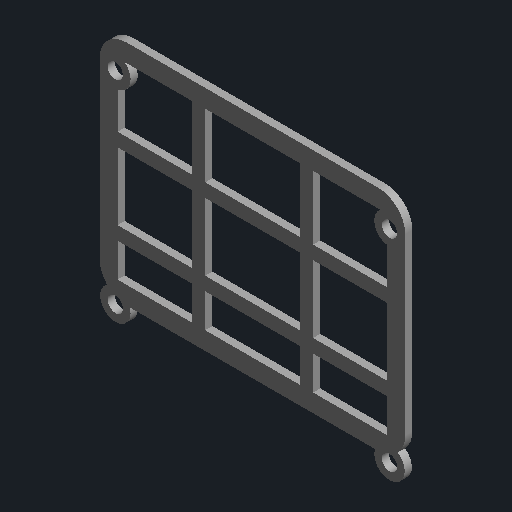
# Autodesk Inventor part: Torso_protector_B
Saved by Autodesk Inventor 2027 (Build 310192060, 192F)
## iProperties
Part Number: Torso_protector_B
Material: Genérico
Document SubType Name: Modelado
Designer: rodri
Appearance: Por defecto
Author: rodri
Autodesk Inventor part; units mm, degrees
ref_plane "Plano de trabajo1" through (0, 0, -29.6) normal (0, 0, 1) x (1, 0, 0)
sketch "Boceto1" plane through (0, 0, -29.6) normal (0, 0, 1) x (1, 0, 0)
  line L0 (-34, 7) -> (34, 7)
  line L1 (34, 7) -> (34, 57.7)
  line L2 (34, 57.7) -> (-34, 57.7)
  line L3 (-34, 57.7) -> (-34, 7)
  constraints: 8 end point, 2 parallel, 1 horizontal, 1 perpendicular
extrude "Extrusión1" add sketch "Boceto1" along normal blind 1.6
fillet "Empalme1" radius 6 4 edges at (-34, 7, -28.8) (-34, 57.7, -28.8) (34, 57.7, -28.8) (34, 7, -28.8)
ref_plane "Plano de trabajo2" through (0, 0, -29.7) normal (0, 0, 1) x (1, 0, 0)
sketch "Boceto2" plane through (0, 0, -29.7) normal (0, 0, 1) x (1, 0, 0)
  line L0 (-30, 11) -> (-13.5, 11)
  line L1 (-13.5, 11) -> (-13.5, 18.5)
  line L2 (-13.5, 18.5) -> (-30, 18.5)
  line L3 (-30, 18.5) -> (-30, 11)
  constraints: 8 end point, 2 parallel, 1 horizontal, 1 perpendicular
extrude "Extrusión2" cut sketch "Boceto2" along normal blind 1.8
ref_plane "Plano de trabajo3" through (0, 0, -29.7) normal (0, 0, 1) x (1, 0, 0)
sketch "Boceto3" plane through (0, 0, -29.7) normal (0, 0, 1) x (1, 0, 0)
  line L0 (-30, 21.5) -> (-13.5, 21.5)
  line L1 (-13.5, 21.5) -> (-13.5, 36.5)
  line L2 (-13.5, 36.5) -> (-30, 36.5)
  line L3 (-30, 36.5) -> (-30, 21.5)
  constraints: 8 end point, 2 parallel, 1 horizontal, 1 perpendicular
extrude "Extrusión3" cut sketch "Boceto3" along normal blind 1.8
ref_plane "Plano de trabajo4" through (0, 0, -29.7) normal (0, 0, 1) x (1, 0, 0)
sketch "Boceto4" plane through (0, 0, -29.7) normal (0, 0, 1) x (1, 0, 0)
  line L0 (-30, 39.5) -> (-13.5, 39.5)
  line L1 (-13.5, 39.5) -> (-13.5, 53.7)
  line L2 (-13.5, 53.7) -> (-30, 53.7)
  line L3 (-30, 53.7) -> (-30, 39.5)
  constraints: 8 end point, 2 parallel, 1 horizontal, 1 perpendicular
extrude "Extrusión4" cut sketch "Boceto4" along normal blind 1.8
ref_plane "Plano de trabajo5" through (0, 0, -29.7) normal (0, 0, 1) x (1, 0, 0)
sketch "Boceto5" plane through (0, 0, -29.7) normal (0, 0, 1) x (1, 0, 0)
  line L0 (-10.5, 11) -> (10.5, 11)
  line L1 (10.5, 11) -> (10.5, 18.5)
  line L2 (10.5, 18.5) -> (-10.5, 18.5)
  line L3 (-10.5, 18.5) -> (-10.5, 11)
  constraints: 8 end point, 2 parallel, 1 horizontal, 1 perpendicular
extrude "Extrusión5" cut sketch "Boceto5" along normal blind 1.8
ref_plane "Plano de trabajo6" through (0, 0, -29.7) normal (0, 0, 1) x (1, 0, 0)
sketch "Boceto6" plane through (0, 0, -29.7) normal (0, 0, 1) x (1, 0, 0)
  line L0 (-10.5, 21.5) -> (10.5, 21.5)
  line L1 (10.5, 21.5) -> (10.5, 36.5)
  line L2 (10.5, 36.5) -> (-10.5, 36.5)
  line L3 (-10.5, 36.5) -> (-10.5, 21.5)
  constraints: 8 end point, 2 parallel, 1 horizontal, 1 perpendicular
extrude "Extrusión6" cut sketch "Boceto6" along normal blind 1.8
ref_plane "Plano de trabajo7" through (0, 0, -29.7) normal (0, 0, 1) x (1, 0, 0)
sketch "Boceto7" plane through (0, 0, -29.7) normal (0, 0, 1) x (1, 0, 0)
  line L0 (-10.5, 39.5) -> (10.5, 39.5)
  line L1 (10.5, 39.5) -> (10.5, 53.7)
  line L2 (10.5, 53.7) -> (-10.5, 53.7)
  line L3 (-10.5, 53.7) -> (-10.5, 39.5)
  constraints: 8 end point, 2 parallel, 1 horizontal, 1 perpendicular
extrude "Extrusión7" cut sketch "Boceto7" along normal blind 1.8
ref_plane "Plano de trabajo8" through (0, 0, -29.7) normal (0, 0, 1) x (1, 0, 0)
sketch "Boceto8" plane through (0, 0, -29.7) normal (0, 0, 1) x (1, 0, 0)
  line L0 (13.5, 11) -> (30, 11)
  line L1 (30, 11) -> (30, 18.5)
  line L2 (30, 18.5) -> (13.5, 18.5)
  line L3 (13.5, 18.5) -> (13.5, 11)
  constraints: 8 end point, 2 parallel, 1 horizontal, 1 perpendicular
extrude "Extrusión8" cut sketch "Boceto8" along normal blind 1.8
ref_plane "Plano de trabajo9" through (0, 0, -29.7) normal (0, 0, 1) x (1, 0, 0)
sketch "Boceto9" plane through (0, 0, -29.7) normal (0, 0, 1) x (1, 0, 0)
  line L0 (13.5, 21.5) -> (30, 21.5)
  line L1 (30, 21.5) -> (30, 36.5)
  line L2 (30, 36.5) -> (13.5, 36.5)
  line L3 (13.5, 36.5) -> (13.5, 21.5)
  constraints: 8 end point, 2 parallel, 1 horizontal, 1 perpendicular
extrude "Extrusión9" cut sketch "Boceto9" along normal blind 1.8
ref_plane "Plano de trabajo10" through (0, 0, -29.7) normal (0, 0, 1) x (1, 0, 0)
sketch "Boceto10" plane through (0, 0, -29.7) normal (0, 0, 1) x (1, 0, 0)
  line L0 (13.5, 39.5) -> (30, 39.5)
  line L1 (30, 39.5) -> (30, 53.7)
  line L2 (30, 53.7) -> (13.5, 53.7)
  line L3 (13.5, 53.7) -> (13.5, 39.5)
  constraints: 8 end point, 2 parallel, 1 horizontal, 1 perpendicular
extrude "Extrusión10" cut sketch "Boceto10" along normal blind 1.8
ref_plane "Plano de trabajo11" through (0, 0, -29.6) normal (0, 0, 1) x (1, 0, 0)
sketch "Boceto11" plane through (0, 0, -29.6) normal (0, 0, 1) x (1, 0, 0)
  circle A0 centre (30.5, 6) radius 3.4
  circle A1 centre (30.5, 51) radius 3.4
  circle A2 centre (-30.5, 6) radius 3.4
  circle A3 centre (-30.5, 51) radius 3.4
  constraints: 4 centre point
extrude "Extrusión11" add sketch "Boceto11" along normal blind 1.6
ref_plane "Plano de trabajo12" through (0, 0, -29.7) normal (0, 0, 1) x (1, 0, 0)
sketch "Boceto12" plane through (0, 0, -29.7) normal (0, 0, 1) x (1, 0, 0)
  circle A0 centre (30.5, 6) radius 1.7
  circle A1 centre (30.5, 51) radius 1.7
  circle A2 centre (-30.5, 6) radius 1.7
  circle A3 centre (-30.5, 51) radius 1.7
  constraints: 4 centre point
extrude "Extrusión12" cut sketch "Boceto12" along normal blind 1.8
ref_plane "Plano de trabajo13" through (0, 0, 0) normal (0, 1, 0) x (0, 0, 1)
ref_plane "Plano de trabajo14" through (0, 0, 0) normal (1, 0, 0) x (0, 0, -1)
